Autodesk Fusion 360 part; units mm, degrees
(part 4 of 28)
  line L1969 (47.4943, 43.3444, -1.4859) -> (47.6302, 43.4803, -1.4859)
  line L1970 (47.6302, 43.4803, -1.4859) -> (47.7857, 43.5933, -1.4859)
  line L1971 (47.7857, 43.5933, -1.4859) -> (47.957, 43.6806, -1.4859)
  line L1972 (47.957, 43.6806, -1.4859) -> (48.1398, 43.74, -1.4859)
  line L1973 (48.1398, 43.74, -1.4859) -> (48.3297, 43.7701, -1.4859)
  line L1974 (48.3297, 43.7701, -1.4859) -> (48.5219, 43.7701, -1.4859)
  line L1975 (48.5219, 43.7701, -1.4859) -> (48.7118, 43.74, -1.4859)
  line L1976 (83.6368, 43.74, -1.4859) -> (83.8196, 43.6806, -1.4859)
  line L1977 (83.8196, 43.6806, -1.4859) -> (83.9909, 43.5933, -1.4859)
  line L1978 (83.9909, 43.5933, -1.4859) -> (84.1464, 43.4803, -1.4859)
  line L1979 (84.1464, 43.4803, -1.4859) -> (84.2823, 43.3444, -1.4859)
  line L1980 (84.2823, 43.3444, -1.4859) -> (84.3953, 43.1889, -1.4859)
  line L1981 (84.3953, 43.1889, -1.4859) -> (84.4826, 43.0176, -1.4859)
  line L1982 (84.4826, 43.0176, -1.4859) -> (84.542, 42.8348, -1.4859)
  line L1983 (84.542, 42.8348, -1.4859) -> (84.572, 42.6449, -1.4859)
  line L1984 (84.572, 42.6449, -1.4859) -> (84.5758, 42.5488, -1.4859)
  line L1985 (84.5758, 42.5488, -1.4859) -> (84.5758, 41.9988, -1.4859)
  line L1986 (84.5758, 41.9988, -1.4859) -> (84.572, 41.9027, -1.4859)
  line L1987 (84.572, 41.9027, -1.4859) -> (84.542, 41.7129, -1.4859)
  line L1988 (84.542, 41.7129, -1.4859) -> (84.4826, 41.53, -1.4859)
  line L1989 (84.4826, 41.53, -1.4859) -> (84.3953, 41.3588, -1.4859)
  line L1990 (84.3953, 41.3588, -1.4859) -> (84.2823, 41.2033, -1.4859)
  line L1991 (84.2823, 41.2033, -1.4859) -> (84.1464, 41.0673, -1.4859)
  line L1992 (84.1464, 41.0673, -1.4859) -> (83.9909, 40.9544, -1.4859)
  line L1993 (83.9909, 40.9544, -1.4859) -> (83.8196, 40.8671, -1.4859)
  line L1994 (83.8196, 40.8671, -1.4859) -> (83.6368, 40.8077, -1.4859)
  line L1995 (83.6368, 40.8077, -1.4859) -> (83.4469, 40.7776, -1.4859)
  line L1996 (83.4469, 40.7776, -1.4859) -> (83.2547, 40.7776, -1.4859)
  line L1997 (83.2547, 40.7776, -1.4859) -> (83.0648, 40.8077, -1.4859)
  line L1998 (83.0648, 40.8077, -1.4859) -> (82.882, 40.8671, -1.4859)
  line L1999 (82.882, 40.8671, -1.4859) -> (82.7107, 40.9544, -1.4859)
  line L2000 (82.7107, 40.9544, -1.4859) -> (82.5552, 41.0673, -1.4859)
  line L2001 (82.5552, 41.0673, -1.4859) -> (82.4193, 41.2033, -1.4859)
  line L2002 (82.4193, 41.2033, -1.4859) -> (82.3063, 41.3588, -1.4859)
  line L2003 (82.3063, 41.3588, -1.4859) -> (82.219, 41.53, -1.4859)
  line L2004 (82.219, 41.53, -1.4859) -> (82.1596, 41.7129, -1.4859)
  line L2005 (82.1596, 41.7129, -1.4859) -> (82.1296, 41.9027, -1.4859)
  line L2006 (82.1296, 41.9027, -1.4859) -> (82.1258, 41.9988, -1.4859)
  line L2007 (82.1258, 41.9988, -1.4859) -> (82.1258, 42.5488, -1.4859)
  line L2008 (82.1258, 42.5488, -1.4859) -> (82.1296, 42.6449, -1.4859)
  line L2009 (82.1296, 42.6449, -1.4859) -> (82.1596, 42.8348, -1.4859)
  line L2010 (82.1596, 42.8348, -1.4859) -> (82.219, 43.0176, -1.4859)
  line L2011 (82.219, 43.0176, -1.4859) -> (82.3063, 43.1889, -1.4859)
  line L2012 (82.3063, 43.1889, -1.4859) -> (82.4193, 43.3444, -1.4859)
  line L2013 (82.4193, 43.3444, -1.4859) -> (82.5552, 43.4803, -1.4859)
  line L2014 (82.5552, 43.4803, -1.4859) -> (82.7107, 43.5933, -1.4859)
  line L2015 (82.7107, 43.5933, -1.4859) -> (82.882, 43.6806, -1.4859)
  line L2016 (82.882, 43.6806, -1.4859) -> (83.0648, 43.74, -1.4859)
  line L2017 (83.0648, 43.74, -1.4859) -> (83.2547, 43.7701, -1.4859)
  line L2018 (83.2547, 43.7701, -1.4859) -> (83.4469, 43.7701, -1.4859)
  line L2019 (83.4469, 43.7701, -1.4859) -> (83.6368, 43.74, -1.4859)
  line L2020 (118.5618, 43.74, -1.4859) -> (118.7446, 43.6806, -1.4859)
  line L2021 (118.7446, 43.6806, -1.4859) -> (118.9159, 43.5933, -1.4859)
  line L2022 (118.9159, 43.5933, -1.4859) -> (119.0714, 43.4803, -1.4859)
  line L2023 (119.0714, 43.4803, -1.4859) -> (119.2073, 43.3444, -1.4859)
  line L2024 (119.2073, 43.3444, -1.4859) -> (119.3203, 43.1889, -1.4859)
  line L2025 (119.3203, 43.1889, -1.4859) -> (119.4076, 43.0176, -1.4859)
  line L2026 (119.4076, 43.0176, -1.4859) -> (119.467, 42.8348, -1.4859)
  line L2027 (119.467, 42.8348, -1.4859) -> (119.497, 42.6449, -1.4859)
  line L2028 (119.497, 42.6449, -1.4859) -> (119.5008, 42.5488, -1.4859)
  line L2029 (119.5008, 42.5488, -1.4859) -> (119.5008, 41.9988, -1.4859)
  line L2030 (119.5008, 41.9988, -1.4859) -> (119.497, 41.9027, -1.4859)
  line L2031 (119.497, 41.9027, -1.4859) -> (119.467, 41.7129, -1.4859)
  line L2032 (119.467, 41.7129, -1.4859) -> (119.4076, 41.53, -1.4859)
  line L2033 (119.4076, 41.53, -1.4859) -> (119.3203, 41.3588, -1.4859)
  line L2034 (119.3203, 41.3588, -1.4859) -> (119.2073, 41.2033, -1.4859)
  line L2035 (119.2073, 41.2033, -1.4859) -> (119.0714, 41.0673, -1.4859)
  line L2036 (119.0714, 41.0673, -1.4859) -> (118.9159, 40.9544, -1.4859)
  line L2037 (118.9159, 40.9544, -1.4859) -> (118.7446, 40.8671, -1.4859)
  line L2038 (118.7446, 40.8671, -1.4859) -> (118.5618, 40.8077, -1.4859)
  line L2039 (118.5618, 40.8077, -1.4859) -> (118.3719, 40.7776, -1.4859)
  line L2040 (118.3719, 40.7776, -1.4859) -> (118.1797, 40.7776, -1.4859)
  line L2041 (118.1797, 40.7776, -1.4859) -> (117.9898, 40.8077, -1.4859)
  line L2042 (117.9898, 40.8077, -1.4859) -> (117.807, 40.8671, -1.4859)
  line L2043 (117.807, 40.8671, -1.4859) -> (117.6357, 40.9544, -1.4859)
  line L2044 (117.6357, 40.9544, -1.4859) -> (117.4802, 41.0673, -1.4859)
  line L2045 (117.4802, 41.0673, -1.4859) -> (117.3443, 41.2033, -1.4859)
  line L2046 (117.3443, 41.2033, -1.4859) -> (117.2313, 41.3588, -1.4859)
  line L2047 (117.2313, 41.3588, -1.4859) -> (117.144, 41.53, -1.4859)
  line L2048 (117.144, 41.53, -1.4859) -> (117.0846, 41.7129, -1.4859)
  line L2049 (117.0846, 41.7129, -1.4859) -> (117.0546, 41.9027, -1.4859)
  line L2050 (117.0546, 41.9027, -1.4859) -> (117.0508, 41.9988, -1.4859)
  line L2051 (117.0508, 41.9988, -1.4859) -> (117.0508, 42.5488, -1.4859)
  line L2052 (117.0508, 42.5488, -1.4859) -> (117.0546, 42.6449, -1.4859)
  line L2053 (117.0546, 42.6449, -1.4859) -> (117.0846, 42.8348, -1.4859)
  line L2054 (117.0846, 42.8348, -1.4859) -> (117.144, 43.0176, -1.4859)
  line L2055 (117.144, 43.0176, -1.4859) -> (117.2313, 43.1889, -1.4859)
  line L2056 (117.2313, 43.1889, -1.4859) -> (117.3443, 43.3444, -1.4859)
  line L2057 (117.3443, 43.3444, -1.4859) -> (117.4802, 43.4803, -1.4859)
  line L2058 (117.4802, 43.4803, -1.4859) -> (117.6357, 43.5933, -1.4859)
  line L2059 (117.6357, 43.5933, -1.4859) -> (117.807, 43.6806, -1.4859)
  line L2060 (117.807, 43.6806, -1.4859) -> (117.9898, 43.74, -1.4859)
  line L2061 (117.9898, 43.74, -1.4859) -> (118.1797, 43.7701, -1.4859)
  line L2062 (118.1797, 43.7701, -1.4859) -> (118.3719, 43.7701, -1.4859)
  line L2063 (118.3719, 43.7701, -1.4859) -> (118.5618, 43.74, -1.4859)
  line L2064 (25.7314, 54.7991, -1.4859) -> (25.8446, 54.7437, -1.4859)
  line L2065 (25.8446, 54.7437, -1.4859) -> (25.9337, 54.6546, -1.4859)
  line L2066 (25.9337, 54.6546, -1.4859) -> (25.9891, 54.5414, -1.4859)
  line L2067 (25.9891, 54.5414, -1.4859) -> (26.005, 54.4322, -1.4859)
  line L2068 (26.005, 54.4322, -1.4859) -> (26.005, 52.1978, -1.4859)
  line L2069 (26.005, 52.1978, -1.4859) -> (25.9891, 52.0886, -1.4859)
  line L2070 (25.9891, 52.0886, -1.4859) -> (25.9337, 51.9754, -1.4859)
  line L2071 (25.9337, 51.9754, -1.4859) -> (25.8446, 51.8863, -1.4859)
  line L2072 (25.8446, 51.8863, -1.4859) -> (25.7314, 51.8309, -1.4859)
  line L2073 (25.7314, 51.8309, -1.4859) -> (25.6222, 51.815, -1.4859)
  line L2074 (25.6222, 51.815, -1.4859) -> (23.9378, 51.815, -1.4859)
  line L2075 (23.9378, 51.815, -1.4859) -> (23.8286, 51.8309, -1.4859)
  line L2076 (23.8286, 51.8309, -1.4859) -> (23.7154, 51.8863, -1.4859)
  line L2077 (23.7154, 51.8863, -1.4859) -> (23.6263, 51.9754, -1.4859)
  line L2078 (23.6263, 51.9754, -1.4859) -> (23.5709, 52.0886, -1.4859)
  line L2079 (23.5709, 52.0886, -1.4859) -> (23.555, 52.1978, -1.4859)
  line L2080 (23.555, 52.1978, -1.4859) -> (23.555, 54.4322, -1.4859)
  line L2081 (23.555, 54.4322, -1.4859) -> (23.5709, 54.5414, -1.4859)
  line L2082 (23.5709, 54.5414, -1.4859) -> (23.6263, 54.6546, -1.4859)
  line L2083 (23.6263, 54.6546, -1.4859) -> (23.7154, 54.7437, -1.4859)
  line L2084 (23.7154, 54.7437, -1.4859) -> (23.8286, 54.7991, -1.4859)
  line L2085 (23.8286, 54.7991, -1.4859) -> (23.9378, 54.815, -1.4859)
  line L2086 (23.9378, 54.815, -1.4859) -> (25.6222, 54.815, -1.4859)
  line L2087 (25.6222, 54.815, -1.4859) -> (25.7314, 54.7991, -1.4859)
  line L2088 (60.6564, 54.7991, -1.4859) -> (60.7696, 54.7437, -1.4859)
  line L2089 (60.7696, 54.7437, -1.4859) -> (60.8587, 54.6546, -1.4859)
  line L2090 (60.8587, 54.6546, -1.4859) -> (60.9141, 54.5414, -1.4859)
  line L2091 (60.9141, 54.5414, -1.4859) -> (60.93, 54.4322, -1.4859)
  line L2092 (60.93, 54.4322, -1.4859) -> (60.93, 52.1978, -1.4859)
  line L2093 (60.93, 52.1978, -1.4859) -> (60.9141, 52.0886, -1.4859)
  line L2094 (60.9141, 52.0886, -1.4859) -> (60.8587, 51.9754, -1.4859)
  line L2095 (60.8587, 51.9754, -1.4859) -> (60.7696, 51.8863, -1.4859)
  line L2096 (60.7696, 51.8863, -1.4859) -> (60.6564, 51.8309, -1.4859)
  line L2097 (60.6564, 51.8309, -1.4859) -> (60.5472, 51.815, -1.4859)
  line L2098 (60.5472, 51.815, -1.4859) -> (58.8628, 51.815, -1.4859)
  line L2099 (58.8628, 51.815, -1.4859) -> (58.7536, 51.8309, -1.4859)
  line L2100 (58.7536, 51.8309, -1.4859) -> (58.6404, 51.8863, -1.4859)
  line L2101 (58.6404, 51.8863, -1.4859) -> (58.5513, 51.9754, -1.4859)
  line L2102 (58.5513, 51.9754, -1.4859) -> (58.4959, 52.0886, -1.4859)
  line L2103 (58.4959, 52.0886, -1.4859) -> (58.48, 52.1978, -1.4859)
  line L2104 (58.48, 52.1978, -1.4859) -> (58.48, 54.4322, -1.4859)
  line L2105 (58.48, 54.4322, -1.4859) -> (58.4959, 54.5414, -1.4859)
  line L2106 (58.4959, 54.5414, -1.4859) -> (58.5513, 54.6546, -1.4859)
  line L2107 (58.5513, 54.6546, -1.4859) -> (58.6404, 54.7437, -1.4859)
  line L2108 (58.6404, 54.7437, -1.4859) -> (58.7536, 54.7991, -1.4859)
  line L2109 (58.7536, 54.7991, -1.4859) -> (58.8628, 54.815, -1.4859)
  line L2110 (58.8628, 54.815, -1.4859) -> (60.5472, 54.815, -1.4859)
  line L2111 (60.5472, 54.815, -1.4859) -> (60.6564, 54.7991, -1.4859)
  line L2112 (95.5814, 54.7991, -1.4859) -> (95.6946, 54.7437, -1.4859)
  line L2113 (95.6946, 54.7437, -1.4859) -> (95.7837, 54.6546, -1.4859)
  line L2114 (95.7837, 54.6546, -1.4859) -> (95.8391, 54.5414, -1.4859)
  line L2115 (95.8391, 54.5414, -1.4859) -> (95.855, 54.4322, -1.4859)
  line L2116 (95.855, 54.4322, -1.4859) -> (95.855, 52.1978, -1.4859)
  line L2117 (95.855, 52.1978, -1.4859) -> (95.8391, 52.0886, -1.4859)
  line L2118 (95.8391, 52.0886, -1.4859) -> (95.7837, 51.9754, -1.4859)
  line L2119 (95.7837, 51.9754, -1.4859) -> (95.6946, 51.8863, -1.4859)
  line L2120 (95.6946, 51.8863, -1.4859) -> (95.5814, 51.8309, -1.4859)
  line L2121 (95.5814, 51.8309, -1.4859) -> (95.4722, 51.815, -1.4859)
  line L2122 (95.4722, 51.815, -1.4859) -> (93.7878, 51.815, -1.4859)
  line L2123 (93.7878, 51.815, -1.4859) -> (93.6786, 51.8309, -1.4859)
  line L2124 (93.6786, 51.8309, -1.4859) -> (93.5654, 51.8863, -1.4859)
  line L2125 (93.5654, 51.8863, -1.4859) -> (93.4763, 51.9754, -1.4859)
  line L2126 (93.4763, 51.9754, -1.4859) -> (93.4209, 52.0886, -1.4859)
  line L2127 (93.4209, 52.0886, -1.4859) -> (93.405, 52.1978, -1.4859)
  line L2128 (93.405, 52.1978, -1.4859) -> (93.405, 54.4322, -1.4859)
  line L2129 (93.405, 54.4322, -1.4859) -> (93.4209, 54.5414, -1.4859)
  line L2130 (93.4209, 54.5414, -1.4859) -> (93.4763, 54.6546, -1.4859)
  line L2131 (93.4763, 54.6546, -1.4859) -> (93.5654, 54.7437, -1.4859)
  line L2132 (93.5654, 54.7437, -1.4859) -> (93.6786, 54.7991, -1.4859)
  line L2133 (93.6786, 54.7991, -1.4859) -> (93.7878, 54.815, -1.4859)
  line L2134 (93.7878, 54.815, -1.4859) -> (95.4722, 54.815, -1.4859)
  line L2135 (95.4722, 54.815, -1.4859) -> (95.5814, 54.7991, -1.4859)
  line L2136 (130.5064, 54.7991, -1.4859) -> (130.6196, 54.7437, -1.4859)
  line L2137 (130.6196, 54.7437, -1.4859) -> (130.7087, 54.6546, -1.4859)
  line L2138 (130.7087, 54.6546, -1.4859) -> (130.7641, 54.5414, -1.4859)
  line L2139 (130.7641, 54.5414, -1.4859) -> (130.78, 54.4322, -1.4859)
  line L2140 (130.78, 54.4322, -1.4859) -> (130.78, 52.1978, -1.4859)
  line L2141 (130.78, 52.1978, -1.4859) -> (130.7641, 52.0886, -1.4859)
  line L2142 (130.7641, 52.0886, -1.4859) -> (130.7087, 51.9754, -1.4859)
  line L2143 (130.7087, 51.9754, -1.4859) -> (130.6196, 51.8863, -1.4859)
  line L2144 (130.6196, 51.8863, -1.4859) -> (130.5064, 51.8309, -1.4859)
  line L2145 (130.5064, 51.8309, -1.4859) -> (130.3972, 51.815, -1.4859)
  line L2146 (130.3972, 51.815, -1.4859) -> (128.7128, 51.815, -1.4859)
  line L2147 (128.7128, 51.815, -1.4859) -> (128.6036, 51.8309, -1.4859)
  line L2148 (128.6036, 51.8309, -1.4859) -> (128.4904, 51.8863, -1.4859)
  line L2149 (128.4904, 51.8863, -1.4859) -> (128.4013, 51.9754, -1.4859)
  line L2150 (128.4013, 51.9754, -1.4859) -> (128.3459, 52.0886, -1.4859)
  line L2151 (128.3459, 52.0886, -1.4859) -> (128.33, 52.1978, -1.4859)
  line L2152 (128.33, 52.1978, -1.4859) -> (128.33, 54.4322, -1.4859)
  line L2153 (128.33, 54.4322, -1.4859) -> (128.3459, 54.5414, -1.4859)
  line L2154 (128.3459, 54.5414, -1.4859) -> (128.4013, 54.6546, -1.4859)
  line L2155 (128.4013, 54.6546, -1.4859) -> (128.4904, 54.7437, -1.4859)
  line L2156 (128.4904, 54.7437, -1.4859) -> (128.6036, 54.7991, -1.4859)
  line L2157 (128.6036, 54.7991, -1.4859) -> (128.7128, 54.815, -1.4859)
  line L2158 (128.7128, 54.815, -1.4859) -> (130.3972, 54.815, -1.4859)
  line L2159 (130.3972, 54.815, -1.4859) -> (130.5064, 54.7991, -1.4859)
  line L2160 (27.566, 54.7812, -1.4859) -> (27.7488, 54.7218, -1.4859)
  line L2161 (27.7488, 54.7218, -1.4859) -> (27.9201, 54.6345, -1.4859)
  line L2162 (27.9201, 54.6345, -1.4859) -> (28.0756, 54.5215, -1.4859)
  line L2163 (28.0756, 54.5215, -1.4859) -> (28.2115, 54.3856, -1.4859)
  line L2164 (28.2115, 54.3856, -1.4859) -> (28.3245, 54.2301, -1.4859)
  line L2165 (28.3245, 54.2301, -1.4859) -> (28.4118, 54.0588, -1.4859)
  line L2166 (28.4118, 54.0588, -1.4859) -> (28.4712, 53.876, -1.4859)
  line L2167 (28.4712, 53.876, -1.4859) -> (28.5012, 53.6861, -1.4859)
  line L2168 (28.5012, 53.6861, -1.4859) -> (28.505, 53.59, -1.4859)
  line L2169 (28.505, 53.59, -1.4859) -> (28.505, 53.04, -1.4859)
  line L2170 (28.505, 53.04, -1.4859) -> (28.5012, 52.9439, -1.4859)
  line L2171 (28.5012, 52.9439, -1.4859) -> (28.4712, 52.754, -1.4859)
  line L2172 (28.4712, 52.754, -1.4859) -> (28.4118, 52.5712, -1.4859)
  line L2173 (28.4118, 52.5712, -1.4859) -> (28.3245, 52.3999, -1.4859)
  line L2174 (28.3245, 52.3999, -1.4859) -> (28.2115, 52.2444, -1.4859)
  line L2175 (28.2115, 52.2444, -1.4859) -> (28.0756, 52.1085, -1.4859)
  line L2176 (28.0756, 52.1085, -1.4859) -> (27.9201, 51.9955, -1.4859)
  line L2177 (27.9201, 51.9955, -1.4859) -> (27.7488, 51.9082, -1.4859)
  line L2178 (27.7488, 51.9082, -1.4859) -> (27.566, 51.8488, -1.4859)
  line L2179 (27.566, 51.8488, -1.4859) -> (27.3761, 51.8188, -1.4859)
  line L2180 (27.3761, 51.8188, -1.4859) -> (27.1839, 51.8188, -1.4859)
  line L2181 (27.1839, 51.8188, -1.4859) -> (26.994, 51.8488, -1.4859)
  line L2182 (26.994, 51.8488, -1.4859) -> (26.8112, 51.9082, -1.4859)
  line L2183 (26.8112, 51.9082, -1.4859) -> (26.6399, 51.9955, -1.4859)
  line L2184 (26.6399, 51.9955, -1.4859) -> (26.4844, 52.1085, -1.4859)
  line L2185 (26.4844, 52.1085, -1.4859) -> (26.3485, 52.2444, -1.4859)
  line L2186 (26.3485, 52.2444, -1.4859) -> (26.2355, 52.3999, -1.4859)
  line L2187 (26.2355, 52.3999, -1.4859) -> (26.1482, 52.5712, -1.4859)
  line L2188 (26.1482, 52.5712, -1.4859) -> (26.0888, 52.754, -1.4859)
  line L2189 (26.0888, 52.754, -1.4859) -> (26.0588, 52.9439, -1.4859)
  line L2190 (26.0588, 52.9439, -1.4859) -> (26.055, 53.04, -1.4859)
  line L2191 (26.055, 53.04, -1.4859) -> (26.055, 53.59, -1.4859)
  line L2192 (26.055, 53.59, -1.4859) -> (26.0588, 53.6861, -1.4859)
  line L2193 (26.0588, 53.6861, -1.4859) -> (26.0888, 53.876, -1.4859)
  line L2194 (26.0888, 53.876, -1.4859) -> (26.1482, 54.0588, -1.4859)
  line L2195 (26.1482, 54.0588, -1.4859) -> (26.2355, 54.2301, -1.4859)
  line L2196 (26.2355, 54.2301, -1.4859) -> (26.3485, 54.3856, -1.4859)
  line L2197 (26.3485, 54.3856, -1.4859) -> (26.4844, 54.5215, -1.4859)
  line L2198 (26.4844, 54.5215, -1.4859) -> (26.6399, 54.6345, -1.4859)
  line L2199 (26.6399, 54.6345, -1.4859) -> (26.8112, 54.7218, -1.4859)
  line L2200 (26.8112, 54.7218, -1.4859) -> (26.994, 54.7812, -1.4859)
  line L2201 (26.994, 54.7812, -1.4859) -> (27.1839, 54.8112, -1.4859)
  line L2202 (27.1839, 54.8112, -1.4859) -> (27.3761, 54.8112, -1.4859)
  line L2203 (27.3761, 54.8112, -1.4859) -> (27.566, 54.7812, -1.4859)
  line L2204 (62.491, 54.7812, -1.4859) -> (62.6738, 54.7218, -1.4859)
  line L2205 (62.6738, 54.7218, -1.4859) -> (62.8451, 54.6345, -1.4859)
  line L2206 (62.8451, 54.6345, -1.4859) -> (63.0006, 54.5215, -1.4859)
  line L2207 (63.0006, 54.5215, -1.4859) -> (63.1365, 54.3856, -1.4859)
  line L2208 (63.1365, 54.3856, -1.4859) -> (63.2495, 54.2301, -1.4859)
  line L2209 (63.2495, 54.2301, -1.4859) -> (63.3368, 54.0588, -1.4859)
  line L2210 (63.3368, 54.0588, -1.4859) -> (63.3962, 53.876, -1.4859)
  line L2211 (63.3962, 53.876, -1.4859) -> (63.4262, 53.6861, -1.4859)
  line L2212 (63.4262, 53.6861, -1.4859) -> (63.43, 53.59, -1.4859)
  line L2213 (63.43, 53.59, -1.4859) -> (63.43, 53.04, -1.4859)
  line L2214 (63.43, 53.04, -1.4859) -> (63.4262, 52.9439, -1.4859)
  line L2215 (63.4262, 52.9439, -1.4859) -> (63.3962, 52.754, -1.4859)
  line L2216 (63.3962, 52.754, -1.4859) -> (63.3368, 52.5712, -1.4859)
  line L2217 (63.3368, 52.5712, -1.4859) -> (63.2495, 52.3999, -1.4859)
  line L2218 (63.2495, 52.3999, -1.4859) -> (63.1365, 52.2444, -1.4859)
  line L2219 (63.1365, 52.2444, -1.4859) -> (63.0006, 52.1085, -1.4859)
  line L2220 (63.0006, 52.1085, -1.4859) -> (62.8451, 51.9955, -1.4859)
  line L2221 (62.8451, 51.9955, -1.4859) -> (62.6738, 51.9082, -1.4859)
  line L2222 (62.6738, 51.9082, -1.4859) -> (62.491, 51.8488, -1.4859)
  line L2223 (62.491, 51.8488, -1.4859) -> (62.3011, 51.8188, -1.4859)
  line L2224 (62.3011, 51.8188, -1.4859) -> (62.1089, 51.8188, -1.4859)
  line L2225 (62.1089, 51.8188, -1.4859) -> (61.919, 51.8488, -1.4859)
  line L2226 (61.919, 51.8488, -1.4859) -> (61.7362, 51.9082, -1.4859)
  line L2227 (61.7362, 51.9082, -1.4859) -> (61.5649, 51.9955, -1.4859)
  line L2228 (61.5649, 51.9955, -1.4859) -> (61.4094, 52.1085, -1.4859)
  line L2229 (61.4094, 52.1085, -1.4859) -> (61.2735, 52.2444, -1.4859)
  line L2230 (61.2735, 52.2444, -1.4859) -> (61.1605, 52.3999, -1.4859)
  line L2231 (61.1605, 52.3999, -1.4859) -> (61.0732, 52.5712, -1.4859)
  line L2232 (61.0732, 52.5712, -1.4859) -> (61.0138, 52.754, -1.4859)
  line L2233 (61.0138, 52.754, -1.4859) -> (60.9838, 52.9439, -1.4859)
  line L2234 (60.9838, 52.9439, -1.4859) -> (60.98, 53.04, -1.4859)
  line L2235 (60.98, 53.04, -1.4859) -> (60.98, 53.59, -1.4859)
  line L2236 (60.98, 53.59, -1.4859) -> (60.9838, 53.6861, -1.4859)
  line L2237 (60.9838, 53.6861, -1.4859) -> (61.0138, 53.876, -1.4859)
  line L2238 (61.0138, 53.876, -1.4859) -> (61.0732, 54.0588, -1.4859)
  line L2239 (61.0732, 54.0588, -1.4859) -> (61.1605, 54.2301, -1.4859)
  line L2240 (61.1605, 54.2301, -1.4859) -> (61.2735, 54.3856, -1.4859)
  line L2241 (61.2735, 54.3856, -1.4859) -> (61.4094, 54.5215, -1.4859)
  line L2242 (61.4094, 54.5215, -1.4859) -> (61.5649, 54.6345, -1.4859)
  line L2243 (61.5649, 54.6345, -1.4859) -> (61.7362, 54.7218, -1.4859)
  line L2244 (61.7362, 54.7218, -1.4859) -> (61.919, 54.7812, -1.4859)
  line L2245 (61.919, 54.7812, -1.4859) -> (62.1089, 54.8112, -1.4859)
  line L2246 (62.1089, 54.8112, -1.4859) -> (62.3011, 54.8112, -1.4859)
  line L2247 (62.3011, 54.8112, -1.4859) -> (62.491, 54.7812, -1.4859)
  line L2248 (97.416, 54.7812, -1.4859) -> (97.5988, 54.7218, -1.4859)
  line L2249 (97.5988, 54.7218, -1.4859) -> (97.7701, 54.6345, -1.4859)
  line L2250 (97.7701, 54.6345, -1.4859) -> (97.9256, 54.5215, -1.4859)
  line L2251 (97.9256, 54.5215, -1.4859) -> (98.0615, 54.3856, -1.4859)
  line L2252 (98.0615, 54.3856, -1.4859) -> (98.1745, 54.2301, -1.4859)
  line L2253 (98.1745, 54.2301, -1.4859) -> (98.2618, 54.0588, -1.4859)
  line L2254 (98.2618, 54.0588, -1.4859) -> (98.3212, 53.876, -1.4859)
  line L2255 (98.3212, 53.876, -1.4859) -> (98.3512, 53.6861, -1.4859)
  line L2256 (98.3512, 53.6861, -1.4859) -> (98.355, 53.59, -1.4859)
  line L2257 (98.355, 53.59, -1.4859) -> (98.355, 53.04, -1.4859)
  line L2258 (98.355, 53.04, -1.4859) -> (98.3512, 52.9439, -1.4859)
  line L2259 (98.3512, 52.9439, -1.4859) -> (98.3212, 52.754, -1.4859)
  line L2260 (98.3212, 52.754, -1.4859) -> (98.2618, 52.5712, -1.4859)
  line L2261 (98.2618, 52.5712, -1.4859) -> (98.1745, 52.3999, -1.4859)
  line L2262 (98.1745, 52.3999, -1.4859) -> (98.0615, 52.2444, -1.4859)
  line L2263 (98.0615, 52.2444, -1.4859) -> (97.9256, 52.1085, -1.4859)
  line L2264 (97.9256, 52.1085, -1.4859) -> (97.7701, 51.9955, -1.4859)
  line L2265 (97.7701, 51.9955, -1.4859) -> (97.5988, 51.9082, -1.4859)
  line L2266 (97.5988, 51.9082, -1.4859) -> (97.416, 51.8488, -1.4859)
  line L2267 (97.416, 51.8488, -1.4859) -> (97.2261, 51.8188, -1.4859)
  line L2268 (97.2261, 51.8188, -1.4859) -> (97.0339, 51.8188, -1.4859)
  line L2269 (97.0339, 51.8188, -1.4859) -> (96.844, 51.8488, -1.4859)
  line L2270 (96.844, 51.8488, -1.4859) -> (96.6612, 51.9082, -1.4859)
  line L2271 (96.6612, 51.9082, -1.4859) -> (96.4899, 51.9955, -1.4859)
  line L2272 (96.4899, 51.9955, -1.4859) -> (96.3344, 52.1085, -1.4859)
  line L2273 (96.3344, 52.1085, -1.4859) -> (96.1985, 52.2444, -1.4859)
  line L2274 (96.1985, 52.2444, -1.4859) -> (96.0855, 52.3999, -1.4859)
  line L2275 (96.0855, 52.3999, -1.4859) -> (95.9982, 52.5712, -1.4859)
  line L2276 (95.9982, 52.5712, -1.4859) -> (95.9388, 52.754, -1.4859)
  line L2277 (95.9388, 52.754, -1.4859) -> (95.9088, 52.9439, -1.4859)
  line L2278 (95.9088, 52.9439, -1.4859) -> (95.905, 53.04, -1.4859)
  line L2279 (95.905, 53.04, -1.4859) -> (95.905, 53.59, -1.4859)
  line L2280 (95.905, 53.59, -1.4859) -> (95.9088, 53.6861, -1.4859)
  line L2281 (95.9088, 53.6861, -1.4859) -> (95.9388, 53.876, -1.4859)
  line L2282 (95.9388, 53.876, -1.4859) -> (95.9982, 54.0588, -1.4859)
  line L2283 (95.9982, 54.0588, -1.4859) -> (96.0855, 54.2301, -1.4859)
  line L2284 (96.0855, 54.2301, -1.4859) -> (96.1985, 54.3856, -1.4859)
  line L2285 (96.1985, 54.3856, -1.4859) -> (96.3344, 54.5215, -1.4859)
  line L2286 (96.3344, 54.5215, -1.4859) -> (96.4899, 54.6345, -1.4859)
  line L2287 (96.4899, 54.6345, -1.4859) -> (96.6612, 54.7218, -1.4859)
  line L2288 (96.6612, 54.7218, -1.4859) -> (96.844, 54.7812, -1.4859)
  line L2289 (96.844, 54.7812, -1.4859) -> (97.0339, 54.8112, -1.4859)
  line L2290 (97.0339, 54.8112, -1.4859) -> (97.2261, 54.8112, -1.4859)
  line L2291 (97.2261, 54.8112, -1.4859) -> (97.416, 54.7812, -1.4859)
  line L2292 (132.341, 54.7812, -1.4859) -> (132.5238, 54.7218, -1.4859)
  line L2293 (132.5238, 54.7218, -1.4859) -> (132.6951, 54.6345, -1.4859)
  line L2294 (132.6951, 54.6345, -1.4859) -> (132.8506, 54.5215, -1.4859)
  line L2295 (132.8506, 54.5215, -1.4859) -> (132.9865, 54.3856, -1.4859)
  line L2296 (132.9865, 54.3856, -1.4859) -> (133.0995, 54.2301, -1.4859)
  line L2297 (133.0995, 54.2301, -1.4859) -> (133.1868, 54.0588, -1.4859)
  line L2298 (133.1868, 54.0588, -1.4859) -> (133.2462, 53.876, -1.4859)
  line L2299 (133.2462, 53.876, -1.4859) -> (133.2762, 53.6861, -1.4859)
  line L2300 (133.2762, 53.6861, -1.4859) -> (133.28, 53.59, -1.4859)
  line L2301 (133.28, 53.59, -1.4859) -> (133.28, 53.04, -1.4859)
  line L2302 (133.28, 53.04, -1.4859) -> (133.2762, 52.9439, -1.4859)
  line L2303 (133.2762, 52.9439, -1.4859) -> (133.2462, 52.754, -1.4859)
  line L2304 (133.2462, 52.754, -1.4859) -> (133.1868, 52.5712, -1.4859)
  line L2305 (133.1868, 52.5712, -1.4859) -> (133.0995, 52.3999, -1.4859)
  line L2306 (133.0995, 52.3999, -1.4859) -> (132.9865, 52.2444, -1.4859)
  line L2307 (132.9865, 52.2444, -1.4859) -> (132.8506, 52.1085, -1.4859)
  line L2308 (132.8506, 52.1085, -1.4859) -> (132.6951, 51.9955, -1.4859)
  line L2309 (132.6951, 51.9955, -1.4859) -> (132.5238, 51.9082, -1.4859)
  line L2310 (132.5238, 51.9082, -1.4859) -> (132.341, 51.8488, -1.4859)
  line L2311 (132.341, 51.8488, -1.4859) -> (132.1511, 51.8188, -1.4859)
  line L2312 (132.1511, 51.8188, -1.4859) -> (131.9589, 51.8188, -1.4859)
  line L2313 (131.9589, 51.8188, -1.4859) -> (131.769, 51.8488, -1.4859)
  line L2314 (131.769, 51.8488, -1.4859) -> (131.5862, 51.9082, -1.4859)
  line L2315 (131.5862, 51.9082, -1.4859) -> (131.4149, 51.9955, -1.4859)
  line L2316 (131.4149, 51.9955, -1.4859) -> (131.2594, 52.1085, -1.4859)
  line L2317 (131.2594, 52.1085, -1.4859) -> (131.1235, 52.2444, -1.4859)
  line L2318 (131.1235, 52.2444, -1.4859) -> (131.0105, 52.3999, -1.4859)
  line L2319 (131.0105, 52.3999, -1.4859) -> (130.9232, 52.5712, -1.4859)
  line L2320 (130.9232, 52.5712, -1.4859) -> (130.8638, 52.754, -1.4859)
  line L2321 (130.8638, 52.754, -1.4859) -> (130.8338, 52.9439, -1.4859)
  line L2322 (130.8338, 52.9439, -1.4859) -> (130.83, 53.04, -1.4859)
  line L2323 (130.83, 53.04, -1.4859) -> (130.83, 53.59, -1.4859)
  line L2324 (130.83, 53.59, -1.4859) -> (130.8338, 53.6861, -1.4859)
  line L2325 (130.8338, 53.6861, -1.4859) -> (130.8638, 53.876, -1.4859)
  line L2326 (130.8638, 53.876, -1.4859) -> (130.9232, 54.0588, -1.4859)
  line L2327 (130.9232, 54.0588, -1.4859) -> (131.0105, 54.2301, -1.4859)
  line L2328 (131.0105, 54.2301, -1.4859) -> (131.1235, 54.3856, -1.4859)
  line L2329 (131.1235, 54.3856, -1.4859) -> (131.2594, 54.5215, -1.4859)
  line L2330 (131.2594, 54.5215, -1.4859) -> (131.4149, 54.6345, -1.4859)
  line L2331 (131.4149, 54.6345, -1.4859) -> (131.5862, 54.7218, -1.4859)
  line L2332 (131.5862, 54.7218, -1.4859) -> (131.769, 54.7812, -1.4859)
  line L2333 (131.769, 54.7812, -1.4859) -> (131.9589, 54.8112, -1.4859)
  line L2334 (131.9589, 54.8112, -1.4859) -> (132.1511, 54.8112, -1.4859)
  line L2335 (132.1511, 54.8112, -1.4859) -> (132.341, 54.7812, -1.4859)
  line L2336 (14.5561, 55.2122, -1.4859) -> (14.6693, 55.1569, -1.4859)
  line L2337 (14.6693, 55.1569, -1.4859) -> (14.7584, 55.0677, -1.4859)
  line L2338 (14.7584, 55.0677, -1.4859) -> (14.8138, 54.9545, -1.4859)
  line L2339 (14.8138, 54.9545, -1.4859) -> (14.8297, 54.8453, -1.4859)
  line L2340 (14.8297, 54.8453, -1.4859) -> (14.8297, 52.6109, -1.4859)
  line L2341 (14.8297, 52.6109, -1.4859) -> (14.8138, 52.5017, -1.4859)
  line L2342 (14.8138, 52.5017, -1.4859) -> (14.7584, 52.3885, -1.4859)
  line L2343 (14.7584, 52.3885, -1.4859) -> (14.6693, 52.2994, -1.4859)
  line L2344 (14.6693, 52.2994, -1.4859) -> (14.5561, 52.244, -1.4859)
  line L2345 (14.5561, 52.244, -1.4859) -> (14.4469, 52.2281, -1.4859)
  line L2346 (14.4469, 52.2281, -1.4859) -> (12.7625, 52.2281, -1.4859)
  line L2347 (12.7625, 52.2281, -1.4859) -> (12.6533, 52.244, -1.4859)
  line L2348 (12.6533, 52.244, -1.4859) -> (12.5401, 52.2994, -1.4859)
  line L2349 (12.5401, 52.2994, -1.4859) -> (12.4509, 52.3885, -1.4859)
  line L2350 (12.4509, 52.3885, -1.4859) -> (12.3956, 52.5017, -1.4859)
  line L2351 (12.3956, 52.5017, -1.4859) -> (12.3797, 52.6109, -1.4859)
  line L2352 (12.3797, 52.6109, -1.4859) -> (12.3797, 54.8453, -1.4859)
  line L2353 (12.3797, 54.8453, -1.4859) -> (12.3956, 54.9545, -1.4859)
  line L2354 (12.3956, 54.9545, -1.4859) -> (12.4509, 55.0677, -1.4859)
  line L2355 (12.4509, 55.0677, -1.4859) -> (12.5401, 55.1569, -1.4859)
  line L2356 (12.5401, 55.1569, -1.4859) -> (12.6533, 55.2122, -1.4859)
  line L2357 (12.6533, 55.2122, -1.4859) -> (12.7625, 55.2281, -1.4859)
  line L2358 (12.7625, 55.2281, -1.4859) -> (14.4469, 55.2281, -1.4859)
  line L2359 (14.4469, 55.2281, -1.4859) -> (14.5561, 55.2122, -1.4859)
  line L2360 (49.4811, 55.2122, -1.4859) -> (49.5943, 55.1569, -1.4859)
  line L2361 (49.5943, 55.1569, -1.4859) -> (49.6834, 55.0677, -1.4859)
  line L2362 (49.6834, 55.0677, -1.4859) -> (49.7388, 54.9545, -1.4859)
  line L2363 (49.7388, 54.9545, -1.4859) -> (49.7547, 54.8453, -1.4859)
  line L2364 (49.7547, 54.8453, -1.4859) -> (49.7547, 52.6109, -1.4859)
  line L2365 (49.7547, 52.6109, -1.4859) -> (49.7388, 52.5017, -1.4859)
  line L2366 (49.7388, 52.5017, -1.4859) -> (49.6834, 52.3885, -1.4859)
  line L2367 (49.6834, 52.3885, -1.4859) -> (49.5943, 52.2994, -1.4859)
  line L2368 (49.5943, 52.2994, -1.4859) -> (49.4811, 52.244, -1.4859)
  line L2369 (49.4811, 52.244, -1.4859) -> (49.3719, 52.2281, -1.4859)
  line L2370 (49.3719, 52.2281, -1.4859) -> (47.6875, 52.2281, -1.4859)
  line L2371 (47.6875, 52.2281, -1.4859) -> (47.5783, 52.244, -1.4859)
  line L2372 (47.5783, 52.244, -1.4859) -> (47.4651, 52.2994, -1.4859)
  line L2373 (47.4651, 52.2994, -1.4859) -> (47.3759, 52.3885, -1.4859)
  line L2374 (47.3759, 52.3885, -1.4859) -> (47.3206, 52.5017, -1.4859)
  line L2375 (47.3206, 52.5017, -1.4859) -> (47.3047, 52.6109, -1.4859)
  line L2376 (47.3047, 52.6109, -1.4859) -> (47.3047, 54.8453, -1.4859)
  line L2377 (47.3047, 54.8453, -1.4859) -> (47.3206, 54.9545, -1.4859)
  line L2378 (47.3206, 54.9545, -1.4859) -> (47.3759, 55.0677, -1.4859)
  line L2379 (47.3759, 55.0677, -1.4859) -> (47.4651, 55.1569, -1.4859)
  line L2380 (47.4651, 55.1569, -1.4859) -> (47.5783, 55.2122, -1.4859)
  line L2381 (47.5783, 55.2122, -1.4859) -> (47.6875, 55.2281, -1.4859)
  line L2382 (47.6875, 55.2281, -1.4859) -> (49.3719, 55.2281, -1.4859)
  line L2383 (49.3719, 55.2281, -1.4859) -> (49.4811, 55.2122, -1.4859)
  line L2384 (84.4061, 55.2122, -1.4859) -> (84.5193, 55.1569, -1.4859)
  line L2385 (84.5193, 55.1569, -1.4859) -> (84.6084, 55.0677, -1.4859)
  line L2386 (84.6084, 55.0677, -1.4859) -> (84.6638, 54.9545, -1.4859)
  line L2387 (84.6638, 54.9545, -1.4859) -> (84.6797, 54.8453, -1.4859)
  line L2388 (84.6797, 54.8453, -1.4859) -> (84.6797, 52.6109, -1.4859)
  line L2389 (84.6797, 52.6109, -1.4859) -> (84.6638, 52.5017, -1.4859)
  line L2390 (84.6638, 52.5017, -1.4859) -> (84.6084, 52.3885, -1.4859)
  line L2391 (84.6084, 52.3885, -1.4859) -> (84.5193, 52.2994, -1.4859)
  line L2392 (84.5193, 52.2994, -1.4859) -> (84.4061, 52.244, -1.4859)
  line L2393 (84.4061, 52.244, -1.4859) -> (84.2969, 52.2281, -1.4859)
  line L2394 (84.2969, 52.2281, -1.4859) -> (82.6125, 52.2281, -1.4859)
  line L2395 (82.6125, 52.2281, -1.4859) -> (82.5033, 52.244, -1.4859)
  line L2396 (82.5033, 52.244, -1.4859) -> (82.3901, 52.2994, -1.4859)
  line L2397 (82.3901, 52.2994, -1.4859) -> (82.3009, 52.3885, -1.4859)
  line L2398 (82.3009, 52.3885, -1.4859) -> (82.2456, 52.5017, -1.4859)
  line L2399 (82.2456, 52.5017, -1.4859) -> (82.2297, 52.6109, -1.4859)
  line L2400 (82.2297, 52.6109, -1.4859) -> (82.2297, 54.8453, -1.4859)
  line L2401 (82.2297, 54.8453, -1.4859) -> (82.2456, 54.9545, -1.4859)
  line L2402 (82.2456, 54.9545, -1.4859) -> (82.3009, 55.0677, -1.4859)
  line L2403 (82.3009, 55.0677, -1.4859) -> (82.3901, 55.1569, -1.4859)
  line L2404 (82.3901, 55.1569, -1.4859) -> (82.5033, 55.2122, -1.4859)
  line L2405 (82.5033, 55.2122, -1.4859) -> (82.6125, 55.2281, -1.4859)
  line L2406 (82.6125, 55.2281, -1.4859) -> (84.2969, 55.2281, -1.4859)
  line L2407 (84.2969, 55.2281, -1.4859) -> (84.4061, 55.2122, -1.4859)
  line L2408 (119.3311, 55.2122, -1.4859) -> (119.4443, 55.1569, -1.4859)
  line L2409 (119.4443, 55.1569, -1.4859) -> (119.5334, 55.0677, -1.4859)
  line L2410 (119.5334, 55.0677, -1.4859) -> (119.5888, 54.9545, -1.4859)
  line L2411 (119.5888, 54.9545, -1.4859) -> (119.6047, 54.8453, -1.4859)
  line L2412 (119.6047, 54.8453, -1.4859) -> (119.6047, 52.6109, -1.4859)
  line L2413 (119.6047, 52.6109, -1.4859) -> (119.5888, 52.5017, -1.4859)
  line L2414 (119.5888, 52.5017, -1.4859) -> (119.5334, 52.3885, -1.4859)
  line L2415 (119.5334, 52.3885, -1.4859) -> (119.4443, 52.2994, -1.4859)
  line L2416 (119.4443, 52.2994, -1.4859) -> (119.3311, 52.244, -1.4859)
  line L2417 (119.3311, 52.244, -1.4859) -> (119.2219, 52.2281, -1.4859)
  line L2418 (119.2219, 52.2281, -1.4859) -> (117.5375, 52.2281, -1.4859)
  line L2419 (117.5375, 52.2281, -1.4859) -> (117.4283, 52.244, -1.4859)
  line L2420 (117.4283, 52.244, -1.4859) -> (117.3151, 52.2994, -1.4859)
  line L2421 (117.3151, 52.2994, -1.4859) -> (117.2259, 52.3885, -1.4859)
  line L2422 (117.2259, 52.3885, -1.4859) -> (117.1706, 52.5017, -1.4859)
  line L2423 (117.1706, 52.5017, -1.4859) -> (117.1547, 52.6109, -1.4859)
  line L2424 (117.1547, 52.6109, -1.4859) -> (117.1547, 54.8453, -1.4859)
  line L2425 (117.1547, 54.8453, -1.4859) -> (117.1706, 54.9545, -1.4859)
  line L2426 (117.1706, 54.9545, -1.4859) -> (117.2259, 55.0677, -1.4859)
  line L2427 (117.2259, 55.0677, -1.4859) -> (117.3151, 55.1569, -1.4859)
  line L2428 (117.3151, 55.1569, -1.4859) -> (117.4283, 55.2122, -1.4859)
  line L2429 (117.4283, 55.2122, -1.4859) -> (117.5375, 55.2281, -1.4859)
  line L2430 (117.5375, 55.2281, -1.4859) -> (119.2219, 55.2281, -1.4859)
  line L2431 (119.2219, 55.2281, -1.4859) -> (119.3311, 55.2122, -1.4859)
  line L2432 (16.4418, 76.4304, -1.4859) -> (16.6229, 76.3554, -1.4859)
  line L2433 (16.6229, 76.3554, -1.4859) -> (16.7859, 76.2465, -1.4859)
  line L2434 (16.7859, 76.2465, -1.4859) -> (16.9245, 76.1079, -1.4859)
  line L2435 (16.9245, 76.1079, -1.4859) -> (17.0334, 75.9449, -1.4859)
  line L2436 (17.0334, 75.9449, -1.4859) -> (17.1085, 75.7638, -1.4859)
  line L2437 (17.1085, 75.7638, -1.4859) -> (17.1467, 75.5715, -1.4859)
  line L2438 (17.1467, 75.5715, -1.4859) -> (17.1515, 75.4735, -1.4859)
  line L2439 (17.1515, 75.4735, -1.4859) -> (17.1515, 74.2735, -1.4859)
  line L2440 (17.1515, 74.2735, -1.4859) -> (17.1467, 74.1755, -1.4859)
  line L2441 (17.1467, 74.1755, -1.4859) -> (17.1085, 73.9832, -1.4859)
  line L2442 (17.1085, 73.9832, -1.4859) -> (17.0334, 73.8021, -1.4859)
  line L2443 (17.0334, 73.8021, -1.4859) -> (16.9245, 73.6391, -1.4859)
  line L2444 (16.9245, 73.6391, -1.4859) -> (16.7859, 73.5005, -1.4859)
  line L2445 (16.7859, 73.5005, -1.4859) -> (16.7629, 73.4851, -1.4859)
  line L2446 (16.7629, 73.4851, -1.4859) -> (16.7629, 65.3433, -1.4859)
  line L2447 (16.7629, 65.3433, -1.4859) -> (16.8912, 65.3016, -1.4859)
  line L2448 (16.8912, 65.3016, -1.4859) -> (17.066, 65.2126, -1.4859)
  line L2449 (17.066, 65.2126, -1.4859) -> (17.2247, 65.0973, -1.4859)
  line L2450 (17.2247, 65.0973, -1.4859) -> (17.3634, 64.9586, -1.4859)
  line L2451 (17.3634, 64.9586, -1.4859) -> (17.4787, 64.7999, -1.4859)
  line L2452 (17.4787, 64.7999, -1.4859) -> (17.5677, 64.6251, -1.4859)
  line L2453 (17.5677, 64.6251, -1.4859) -> (17.6284, 64.4386, -1.4859)
  line L2454 (17.6284, 64.4386, -1.4859) -> (17.659, 64.2448, -1.4859)
  line L2455 (17.659, 64.2448, -1.4859) -> (17.659, 64.0487, -1.4859)
  line L2456 (17.659, 64.0487, -1.4859) -> (17.6284, 63.855, -1.4859)
  line L2457 (17.6284, 63.855, -1.4859) -> (17.5677, 63.6684, -1.4859)
  line L2458 (17.5677, 63.6684, -1.4859) -> (17.4787, 63.4936, -1.4859)
  line L2459 (17.4787, 63.4936, -1.4859) -> (17.3634, 63.335, -1.4859)
  line L2460 (17.3634, 63.335, -1.4859) -> (17.2247, 63.1963, -1.4859)
  line L2461 (17.2247, 63.1963, -1.4859) -> (17.066, 63.081, -1.4859)
  line L2462 (17.066, 63.081, -1.4859) -> (16.8912, 62.9919, -1.4859)
  line L2463 (16.8912, 62.9919, -1.4859) -> (16.7047, 62.9313, -1.4859)
  line L2464 (16.7297, 62.9563) -> (16.7297, 62.9563)
  line L2465 (16.7047, 62.9313, -1.4859) -> (16.7047, 55.068, -1.4859)
  line L2466 (16.7047, 55.068, -1.4859) -> (16.7447, 55.0476, -1.4859)
  line L2467 (16.7447, 55.0476, -1.4859) -> (16.9003, 54.9346, -1.4859)
  line L2468 (16.9003, 54.9346, -1.4859) -> (17.0362, 54.7987, -1.4859)
  line L2469 (17.0362, 54.7987, -1.4859) -> (17.1492, 54.6432, -1.4859)
  line L2470 (17.1492, 54.6432, -1.4859) -> (17.2364, 54.4719, -1.4859)
  line L2471 (17.2364, 54.4719, -1.4859) -> (17.2958, 54.2891, -1.4859)
  line L2472 (17.2958, 54.2891, -1.4859) -> (17.3259, 54.0992, -1.4859)
  line L2473 (17.3259, 54.0992, -1.4859) -> (17.3297, 54.0031, -1.4859)
  line L2474 (17.3297, 54.0031, -1.4859) -> (17.3297, 53.4531, -1.4859)
  line L2475 (17.3297, 53.4531, -1.4859) -> (17.3259, 53.357, -1.4859)
  line L2476 (17.3259, 53.357, -1.4859) -> (17.2958, 53.1671, -1.4859)
  line L2477 (17.2958, 53.1671, -1.4859) -> (17.2364, 52.9843, -1.4859)
  line L2478 (17.2364, 52.9843, -1.4859) -> (17.1492, 52.8131, -1.4859)
  line L2479 (17.1492, 52.8131, -1.4859) -> (17.0362, 52.6575, -1.4859)
  line L2480 (17.0362, 52.6575, -1.4859) -> (16.9003, 52.5216, -1.4859)
  line L2481 (16.9003, 52.5216, -1.4859) -> (16.7447, 52.4086, -1.4859)
  line L2482 (16.7447, 52.4086, -1.4859) -> (16.5735, 52.3214, -1.4859)
  line L2483 (16.5735, 52.3214, -1.4859) -> (16.3907, 52.262, -1.4859)
  line L2484 (16.3907, 52.262, -1.4859) -> (16.2008, 52.2319, -1.4859)
  line L2485 (16.2008, 52.2319, -1.4859) -> (16.0086, 52.2319, -1.4859)
  line L2486 (16.0086, 52.2319, -1.4859) -> (15.8187, 52.262, -1.4859)
  line L2487 (15.8187, 52.262, -1.4859) -> (15.6359, 52.3214, -1.4859)
  line L2488 (15.6359, 52.3214, -1.4859) -> (15.4646, 52.4086, -1.4859)
  line L2489 (15.4646, 52.4086, -1.4859) -> (15.3091, 52.5216, -1.4859)
  line L2490 (15.3091, 52.5216, -1.4859) -> (15.1732, 52.6575, -1.4859)
  line L2491 (15.1732, 52.6575, -1.4859) -> (15.0602, 52.8131, -1.4859)
  line L2492 (15.0602, 52.8131, -1.4859) -> (14.9729, 52.9843, -1.4859)
  line L2493 (14.9729, 52.9843, -1.4859) -> (14.9135, 53.1671, -1.4859)
  line L2494 (14.9135, 53.1671, -1.4859) -> (14.8835, 53.357, -1.4859)
  line L2495 (14.8835, 53.357, -1.4859) -> (14.8797, 53.4531, -1.4859)
  line L2496 (14.8797, 53.4531, -1.4859) -> (14.8797, 54.0031, -1.4859)
  line L2497 (14.8797, 54.0031, -1.4859) -> (14.8835, 54.0992, -1.4859)
  line L2498 (14.8835, 54.0992, -1.4859) -> (14.9135, 54.2891, -1.4859)
  line L2499 (14.9135, 54.2891, -1.4859) -> (14.9729, 54.4719, -1.4859)
  line L2500 (14.9729, 54.4719, -1.4859) -> (15.0602, 54.6432, -1.4859)
  line L2501 (15.0602, 54.6432, -1.4859) -> (15.1732, 54.7987, -1.4859)
  line L2502 (15.1732, 54.7987, -1.4859) -> (15.3091, 54.9346, -1.4859)
  line L2503 (15.3091, 54.9346, -1.4859) -> (15.4646, 55.0476, -1.4859)
  line L2504 (15.4646, 55.0476, -1.4859) -> (15.5047, 55.068, -1.4859)
  line L2505 (15.5047, 55.068, -1.4859) -> (15.5047, 62.9691, -1.4859)
  line L2506 (15.5047, 62.9691, -1.4859) -> (15.4345, 62.9919, -1.4859)
  line L2507 (15.4345, 62.9919, -1.4859) -> (15.2598, 63.081, -1.4859)
  line L2508 (15.2598, 63.081, -1.4859) -> (15.1011, 63.1963, -1.4859)
  line L2509 (15.1011, 63.1963, -1.4859) -> (14.9624, 63.335, -1.4859)
  line L2510 (14.9624, 63.335, -1.4859) -> (14.8471, 63.4936, -1.4859)
  line L2511 (14.8471, 63.4936, -1.4859) -> (14.758, 63.6684, -1.4859)
  line L2512 (14.758, 63.6684, -1.4859) -> (14.6974, 63.855, -1.4859)
  line L2513 (14.6974, 63.855, -1.4859) -> (14.6667, 64.0487, -1.4859)
  line L2514 (14.6667, 64.0487, -1.4859) -> (14.6667, 64.2448, -1.4859)
  line L2515 (14.6667, 64.2448, -1.4859) -> (14.6974, 64.4386, -1.4859)
  line L2516 (14.6974, 64.4386, -1.4859) -> (14.758, 64.6251, -1.4859)
  line L2517 (14.758, 64.6251, -1.4859) -> (14.8471, 64.7999, -1.4859)
  line L2518 (14.8471, 64.7999, -1.4859) -> (14.9624, 64.9586, -1.4859)
  line L2519 (14.9624, 64.9586, -1.4859) -> (15.1011, 65.0973, -1.4859)
  line L2520 (15.1011, 65.0973, -1.4859) -> (15.2598, 65.2126, -1.4859)
  line L2521 (15.2598, 65.2126, -1.4859) -> (15.4345, 65.3016, -1.4859)
  line L2522 (15.4345, 65.3016, -1.4859) -> (15.5629, 65.3433, -1.4859)
  line L2523 (15.5629, 65.3433, -1.4859) -> (15.5629, 73.4699, -1.4859)
  line L2524 (15.5629, 73.4699, -1.4859) -> (15.5171, 73.5005, -1.4859)
  line L2525 (15.5171, 73.5005, -1.4859) -> (15.3785, 73.6391, -1.4859)
  line L2526 (15.3785, 73.6391, -1.4859) -> (15.2696, 73.8021, -1.4859)
  line L2527 (15.2696, 73.8021, -1.4859) -> (15.1946, 73.9832, -1.4859)
  line L2528 (15.1946, 73.9832, -1.4859) -> (15.1563, 74.1755, -1.4859)
  line L2529 (15.1563, 74.1755, -1.4859) -> (15.1515, 74.2735, -1.4859)
  line L2530 (15.1515, 74.2735, -1.4859) -> (15.1515, 75.4735, -1.4859)
  line L2531 (15.1515, 75.4735, -1.4859) -> (15.1563, 75.5715, -1.4859)
  line L2532 (15.1563, 75.5715, -1.4859) -> (15.1946, 75.7638, -1.4859)
  line L2533 (15.1946, 75.7638, -1.4859) -> (15.2696, 75.9449, -1.4859)
  line L2534 (15.2696, 75.9449, -1.4859) -> (15.3785, 76.1079, -1.4859)
  line L2535 (15.3785, 76.1079, -1.4859) -> (15.5171, 76.2465, -1.4859)
  line L2536 (15.5171, 76.2465, -1.4859) -> (15.6801, 76.3554, -1.4859)
  line L2537 (15.6801, 76.3554, -1.4859) -> (15.8612, 76.4304, -1.4859)
  line L2538 (15.8612, 76.4304, -1.4859) -> (16.0535, 76.4687, -1.4859)
  line L2539 (16.0535, 76.4687, -1.4859) -> (16.2495, 76.4687, -1.4859)
  line L2540 (16.2495, 76.4687, -1.4859) -> (16.4418, 76.4304, -1.4859)
  line L2541 (51.3668, 76.4304, -1.4859) -> (51.5479, 76.3554, -1.4859)
  line L2542 (51.5479, 76.3554, -1.4859) -> (51.7109, 76.2465, -1.4859)
  line L2543 (51.7109, 76.2465, -1.4859) -> (51.8495, 76.1079, -1.4859)
  line L2544 (51.8495, 76.1079, -1.4859) -> (51.9584, 75.9449, -1.4859)
  line L2545 (51.9584, 75.9449, -1.4859) -> (52.0335, 75.7638, -1.4859)
  line L2546 (52.0335, 75.7638, -1.4859) -> (52.0717, 75.5715, -1.4859)
  line L2547 (52.0717, 75.5715, -1.4859) -> (52.0765, 75.4735, -1.4859)
  line L2548 (52.0765, 75.4735, -1.4859) -> (52.0765, 74.2735, -1.4859)
  line L2549 (52.0765, 74.2735, -1.4859) -> (52.0717, 74.1755, -1.4859)
  line L2550 (52.0717, 74.1755, -1.4859) -> (52.0335, 73.9832, -1.4859)
  line L2551 (52.0335, 73.9832, -1.4859) -> (51.9584, 73.8021, -1.4859)
  line L2552 (51.9584, 73.8021, -1.4859) -> (51.8495, 73.6391, -1.4859)
  line L2553 (51.8495, 73.6391, -1.4859) -> (51.7109, 73.5005, -1.4859)
  line L2554 (51.7109, 73.5005, -1.4859) -> (51.6879, 73.4851, -1.4859)
  line L2555 (51.6879, 73.4851, -1.4859) -> (51.6879, 65.3433, -1.4859)
  line L2556 (51.6879, 65.3433, -1.4859) -> (51.8162, 65.3016, -1.4859)
  line L2557 (51.8162, 65.3016, -1.4859) -> (51.991, 65.2126, -1.4859)
  line L2558 (51.991, 65.2126, -1.4859) -> (52.1497, 65.0973, -1.4859)
  line L2559 (52.1497, 65.0973, -1.4859) -> (52.2884, 64.9586, -1.4859)
  line L2560 (52.2884, 64.9586, -1.4859) -> (52.4037, 64.7999, -1.4859)
  line L2561 (52.4037, 64.7999, -1.4859) -> (52.4927, 64.6251, -1.4859)
  line L2562 (52.4927, 64.6251, -1.4859) -> (52.5534, 64.4386, -1.4859)
  line L2563 (52.5534, 64.4386, -1.4859) -> (52.584, 64.2448, -1.4859)
  line L2564 (52.584, 64.2448, -1.4859) -> (52.584, 64.0487, -1.4859)
  line L2565 (52.584, 64.0487, -1.4859) -> (52.5533, 63.855, -1.4859)
  line L2566 (52.5533, 63.855, -1.4859) -> (52.4927, 63.6684, -1.4859)
  line L2567 (52.4927, 63.6684, -1.4859) -> (52.4037, 63.4936, -1.4859)
  line L2568 (52.4037, 63.4936, -1.4859) -> (52.2884, 63.335, -1.4859)
  line L2569 (52.2884, 63.335, -1.4859) -> (52.1497, 63.1963, -1.4859)
  line L2570 (52.1497, 63.1963, -1.4859) -> (51.991, 63.081, -1.4859)
  line L2571 (51.991, 63.081, -1.4859) -> (51.8162, 62.9919, -1.4859)
  line L2572 (51.8162, 62.9919, -1.4859) -> (51.6297, 62.9313, -1.4859)
  line L2573 (51.6547, 62.9563) -> (51.6547, 62.9563)
  line L2574 (51.6297, 62.9313, -1.4859) -> (51.6297, 55.068, -1.4859)
  line L2575 (51.6297, 55.068, -1.4859) -> (51.6697, 55.0476, -1.4859)
  line L2576 (51.6697, 55.0476, -1.4859) -> (51.8253, 54.9346, -1.4859)
  line L2577 (51.8253, 54.9346, -1.4859) -> (51.9612, 54.7987, -1.4859)
  line L2578 (51.9612, 54.7987, -1.4859) -> (52.0742, 54.6432, -1.4859)
  line L2579 (52.0742, 54.6432, -1.4859) -> (52.1614, 54.4719, -1.4859)
  line L2580 (52.1614, 54.4719, -1.4859) -> (52.2208, 54.2891, -1.4859)
  line L2581 (52.2208, 54.2891, -1.4859) -> (52.2509, 54.0992, -1.4859)
  line L2582 (52.2509, 54.0992, -1.4859) -> (52.2547, 54.0031, -1.4859)
  line L2583 (52.2547, 54.0031, -1.4859) -> (52.2547, 53.4531, -1.4859)
  line L2584 (52.2547, 53.4531, -1.4859) -> (52.2509, 53.357, -1.4859)
  line L2585 (52.2509, 53.357, -1.4859) -> (52.2208, 53.1671, -1.4859)
  line L2586 (52.2208, 53.1671, -1.4859) -> (52.1614, 52.9843, -1.4859)
  line L2587 (52.1614, 52.9843, -1.4859) -> (52.0742, 52.8131, -1.4859)
  line L2588 (52.0742, 52.8131, -1.4859) -> (51.9612, 52.6575, -1.4859)
  line L2589 (51.9612, 52.6575, -1.4859) -> (51.8253, 52.5216, -1.4859)
  line L2590 (51.8253, 52.5216, -1.4859) -> (51.6697, 52.4086, -1.4859)
  line L2591 (51.6697, 52.4086, -1.4859) -> (51.4985, 52.3214, -1.4859)
  line L2592 (51.4985, 52.3214, -1.4859) -> (51.3157, 52.262, -1.4859)
  line L2593 (51.3157, 52.262, -1.4859) -> (51.1258, 52.2319, -1.4859)
  line L2594 (51.1258, 52.2319, -1.4859) -> (50.9336, 52.2319, -1.4859)
  line L2595 (50.9336, 52.2319, -1.4859) -> (50.7437, 52.262, -1.4859)
  line L2596 (50.7437, 52.262, -1.4859) -> (50.5609, 52.3214, -1.4859)
  line L2597 (50.5609, 52.3214, -1.4859) -> (50.3896, 52.4086, -1.4859)
  line L2598 (50.3896, 52.4086, -1.4859) -> (50.2341, 52.5216, -1.4859)
  line L2599 (50.2341, 52.5216, -1.4859) -> (50.0982, 52.6575, -1.4859)
  line L2600 (50.0982, 52.6575, -1.4859) -> (49.9852, 52.8131, -1.4859)
  line L2601 (49.9852, 52.8131, -1.4859) -> (49.8979, 52.9843, -1.4859)
  line L2602 (49.8979, 52.9843, -1.4859) -> (49.8385, 53.1671, -1.4859)
  line L2603 (49.8385, 53.1671, -1.4859) -> (49.8085, 53.357, -1.4859)
  line L2604 (49.8085, 53.357, -1.4859) -> (49.8047, 53.4531, -1.4859)
  line L2605 (49.8047, 53.4531, -1.4859) -> (49.8047, 54.0031, -1.4859)
  line L2606 (49.8047, 54.0031, -1.4859) -> (49.8085, 54.0992, -1.4859)
  line L2607 (49.8085, 54.0992, -1.4859) -> (49.8385, 54.2891, -1.4859)
  line L2608 (49.8385, 54.2891, -1.4859) -> (49.8979, 54.4719, -1.4859)
  line L2609 (49.8979, 54.4719, -1.4859) -> (49.9852, 54.6432, -1.4859)
  line L2610 (49.9852, 54.6432, -1.4859) -> (50.0982, 54.7987, -1.4859)
  line L2611 (50.0982, 54.7987, -1.4859) -> (50.2341, 54.9346, -1.4859)
  line L2612 (50.2341, 54.9346, -1.4859) -> (50.3896, 55.0476, -1.4859)
  line L2613 (50.3896, 55.0476, -1.4859) -> (50.4297, 55.068, -1.4859)
  line L2614 (50.4297, 55.068, -1.4859) -> (50.4297, 62.9691, -1.4859)
  line L2615 (50.4297, 62.9691, -1.4859) -> (50.3595, 62.9919, -1.4859)
  line L2616 (50.3595, 62.9919, -1.4859) -> (50.1848, 63.081, -1.4859)
  line L2617 (50.1848, 63.081, -1.4859) -> (50.0261, 63.1963, -1.4859)
  line L2618 (50.0261, 63.1963, -1.4859) -> (49.8874, 63.335, -1.4859)
  line L2619 (49.8874, 63.335, -1.4859) -> (49.7721, 63.4936, -1.4859)
  line L2620 (49.7721, 63.4936, -1.4859) -> (49.683, 63.6684, -1.4859)
  line L2621 (49.683, 63.6684, -1.4859) -> (49.6224, 63.855, -1.4859)
  line L2622 (49.6224, 63.855, -1.4859) -> (49.5917, 64.0487, -1.4859)
  line L2623 (49.5917, 64.0487, -1.4859) -> (49.5917, 64.2448, -1.4859)
  line L2624 (49.5917, 64.2448, -1.4859) -> (49.6224, 64.4386, -1.4859)
  line L2625 (49.6224, 64.4386, -1.4859) -> (49.683, 64.6251, -1.4859)
  line L2626 (49.683, 64.6251, -1.4859) -> (49.7721, 64.7999, -1.4859)
  line L2627 (49.7721, 64.7999, -1.4859) -> (49.8874, 64.9586, -1.4859)
  line L2628 (49.8874, 64.9586, -1.4859) -> (50.0261, 65.0973, -1.4859)
  line L2629 (50.0261, 65.0973, -1.4859) -> (50.1848, 65.2126, -1.4859)
  line L2630 (50.1848, 65.2126, -1.4859) -> (50.3595, 65.3016, -1.4859)
  line L2631 (50.3595, 65.3016, -1.4859) -> (50.4879, 65.3433, -1.4859)
  line L2632 (50.4879, 65.3433, -1.4859) -> (50.4879, 73.4699, -1.4859)
  line L2633 (50.4879, 73.4699, -1.4859) -> (50.4421, 73.5005, -1.4859)
  line L2634 (50.4421, 73.5005, -1.4859) -> (50.3035, 73.6391, -1.4859)
  line L2635 (50.3035, 73.6391, -1.4859) -> (50.1946, 73.8021, -1.4859)
  line L2636 (50.1946, 73.8021, -1.4859) -> (50.1196, 73.9832, -1.4859)
  line L2637 (50.1196, 73.9832, -1.4859) -> (50.0813, 74.1755, -1.4859)
  line L2638 (50.0813, 74.1755, -1.4859) -> (50.0765, 74.2735, -1.4859)
  line L2639 (50.0765, 74.2735, -1.4859) -> (50.0765, 75.4735, -1.4859)
  line L2640 (50.0765, 75.4735, -1.4859) -> (50.0813, 75.5715, -1.4859)
  line L2641 (50.0813, 75.5715, -1.4859) -> (50.1196, 75.7638, -1.4859)
  line L2642 (50.1196, 75.7638, -1.4859) -> (50.1946, 75.9449, -1.4859)
  line L2643 (50.1946, 75.9449, -1.4859) -> (50.3035, 76.1079, -1.4859)
  line L2644 (50.3035, 76.1079, -1.4859) -> (50.4421, 76.2465, -1.4859)
  line L2645 (50.4421, 76.2465, -1.4859) -> (50.6051, 76.3554, -1.4859)
  line L2646 (50.6051, 76.3554, -1.4859) -> (50.7862, 76.4304, -1.4859)
  line L2647 (50.7862, 76.4304, -1.4859) -> (50.9785, 76.4687, -1.4859)
  line L2648 (50.9785, 76.4687, -1.4859) -> (51.1745, 76.4687, -1.4859)
  line L2649 (51.1745, 76.4687, -1.4859) -> (51.3668, 76.4304, -1.4859)
  line L2650 (86.2918, 76.4304, -1.4859) -> (86.4729, 76.3554, -1.4859)
  line L2651 (86.4729, 76.3554, -1.4859) -> (86.6359, 76.2465, -1.4859)
  line L2652 (86.6359, 76.2465, -1.4859) -> (86.7745, 76.1079, -1.4859)
  line L2653 (86.7745, 76.1079, -1.4859) -> (86.8834, 75.9449, -1.4859)
  line L2654 (86.8834, 75.9449, -1.4859) -> (86.9585, 75.7638, -1.4859)
  line L2655 (86.9585, 75.7638, -1.4859) -> (86.9967, 75.5715, -1.4859)
  line L2656 (86.9967, 75.5715, -1.4859) -> (87.0015, 75.4735, -1.4859)
  line L2657 (87.0015, 75.4735, -1.4859) -> (87.0015, 74.2735, -1.4859)
  line L2658 (87.0015, 74.2735, -1.4859) -> (86.9967, 74.1755, -1.4859)
  line L2659 (86.9967, 74.1755, -1.4859) -> (86.9585, 73.9832, -1.4859)
  line L2660 (86.9585, 73.9832, -1.4859) -> (86.8834, 73.8021, -1.4859)
  line L2661 (86.8834, 73.8021, -1.4859) -> (86.7745, 73.6391, -1.4859)
  line L2662 (86.7745, 73.6391, -1.4859) -> (86.6359, 73.5005, -1.4859)
  line L2663 (86.6359, 73.5005, -1.4859) -> (86.6129, 73.4851, -1.4859)